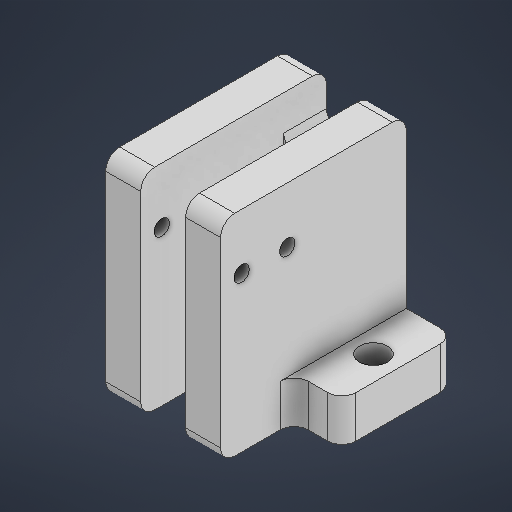
# Autodesk Inventor part: 6_06_support_detection2
Saved by Autodesk Inventor 2026 (Build 300175000, 175)
## iProperties
Created: 2025-06-18
Part Number: 6_06_support_detection2
Material: Générique
Document SubType Name: Modeling
Designer: Diogo
Density: 1 g/cm^3
Appearance: Par défaut
Author: Diogo
Autodesk Inventor part; units mm, degrees
ref_plane "YZ Plane" through (0, 0, 0) normal (1, 0, 0) x (0, 1, 0)
ref_plane "XZ Plane" through (0, 0, 0) normal (0, 1, 0) x (-1, 0, 0)
ref_plane "XY Plane" through (0, 0, 0) normal (0, 0, 1) x (1, 0, 0)
sketch "Esquisse1" plane through (0, 0, 0) normal (0, 0, 1) x (1, 0, 0)
  line L0 (0, 0) -> (11.8, 0)
  line L1 (11.8, 0) -> (11.8, 15)
  line L2 (11.8, 15) -> (18.2, 15)
  line L3 (18.2, 15) -> (18.2, 0)
  line L4 (18.2, 0) -> (30, 0)
  line L5 (30, 0) -> (30, 6)
  line L6 (30, 6) -> (23.2, 6)
  line L7 (23.2, 6) -> (23.2, 30)
  line L8 (23.2, 30) -> (18.2, 30)
  line L9 (18.2, 30) -> (18.2, 23)
  line L10 (18.2, 23) -> (11.8, 23)
  line L11 (11.8, 23) -> (11.8, 30)
  line L12 (6.8, 30) -> (6.8, 6)
  line L13 (6.8, 6) -> (0, 6)
  line L14 (0, 6) -> (0, 0)
  line L15 (0, 0) -> (11.8, 0)
  line L16 (11.8, 30) -> (6.8, 30)
  dimension "d0" = 11.8
  dimension "d1" = 15
  dimension "d2" = 6.4
  dimension "d3" = 11.8
  dimension "d4" = 6
  dimension "d5" = 6.8
  dimension "d6" = 24
  dimension "d7" = 7
  dimension "d8" = 6.8
  dimension "d9" = 5
  constraints: 34 end point, 11 point on line, 9 perpendicular, 2 horizontal, 1 collinear, 1 parallel
  measures "d0" distance of L0.start L0.end
  measures "d1" distance of L0.end L1.end
  measures "d2" distance of L1.end L2.end
  measures "d3" distance of L3.end L4.end
  measures "d4" distance of L4.end L5.end
  measures "d5" distance of L5.end L6.end
  measures "d6" distance of L6.end L7.end
  measures "d7" distance of L8.end L9.end
  measures "d8" distance of L12.end L13.end
  measures "d9" distance of L11.end L12.start
extrude "Extrusion1" add sketch "Esquisse1" along normal mid plane 26.5
sketch "Esquisse2" plane through (0, 0, 0) normal (0, 1, 0) x (-1, 0, 0)
  line L0 (0, 13.25) -> (-11.8, 13.25) projected
  line L1 (-18.2, -13.25) -> (-18.2, 13.25) projected
  line L2 (-11.8, 13.25) -> (-18.2, 13.25)
  line L3 (-18.2, 13.25) -> (-18.2, -7.15)
  line L4 (-18.2, -7.15) -> (-11.8, -7.15)
  line L5 (-11.8, -7.15) -> (-11.8, 13.25)
  line L6 (0, -13.25) -> (0, 13.25) projected
  line L7 (-6.8, -13.25) -> (-6.8, 13.25) projected
  line L8 (0, 13.25) -> (-6.8, 13.25)
  line L9 (-6.8, 13.25) -> (-6.8, 2.75)
  line L10 (-6.8, 2.75) -> (0, 2.75)
  line L11 (0, 2.75) -> (0, 13.25)
  line L12 (-30, -13.25) -> (-30, 13.25) projected
  line L13 (-23.2, -13.25) -> (-23.2, 13.25) projected
  line L14 (-30, 13.25) -> (-23.2, 13.25)
  line L15 (-23.2, 13.25) -> (-23.2, 2.75)
  line L16 (-23.2, 2.75) -> (-30, 2.75)
  line L17 (-30, 2.75) -> (-30, 13.25)
  point P0 (0, 0)
  point P1 (-18.2, 13.25)
  dimension "d12" = 20.4
  dimension "d38" = 10.5
  dimension "d39" = 10.5
  constraints: 24 end point, 6 parallel, 3 horizontal, 3 perpendicular, 3 point on line
  measures "d12" distance of L3.end L2.end
  measures "d38" distance of L9.end L8.end
  measures "d39" distance of L14.end L15.end
extrude "Extrusion2" cut sketch "Esquisse2" along normal through all
sketch "Esquisse3" plane through (0, 6, 13.25) normal (0, 1, 0) x (1, 0, 0)
  line L0 (0, 26.5) -> (0, 0) projected
  line L1 (0, 26.5) -> (6.8, 26.5) projected
  point P0 (0, 13.25)
  point P1 (3.5, 18.5)
  dimension "d23" = 3.5
  dimension "d37" = 8
  measures "d23" distance from line of L0 point (3.5, 18.5)
  measures "d37" distance from line of L1 point (3.5, 18.5)
hole "Perçage1" at (3.5, 6, -5.25) direction (0, -1, 0) diameter 4 end through all
pattern_linear "Réseau rectangulaire1" count 2 spacing 23 along (1, 0, 0) of "Perçage1"
sketch "Esquisse4" plane through (6.8, 6, 13.25) normal (-1, 0, 0) x (0, 0, 1)
  circle A0 centre (-3, 16.05) radius 1.1
  line L0 (0, 24) -> (0, 0) projected
  circle A1 centre (-9.5, 16.05) radius 1.1
  line L1 (0, -6) -> (6.0526, -6) construction
  line L2 (6.0526, -6) -> (6.0526, 20) construction
  line L3 (6.0526, 20) -> (0, 20) construction
  line L4 (0, 20) -> (0, -6) construction
  line L5 (-26.5, 24) -> (0, 24) projected
  line L6 (-21.4941, 16.05) -> (1.7379, 16.05) construction
  line L7 (-26.5, 0) -> (-26.5, 24) construction
  point P0 (-13.25, -6)
  dimension "d27" = 2.2
  dimension "d29" = 2.2
  dimension "d30" = 6.5
  dimension "d31" = 26
  dimension "d32" = 7.95
  dimension "d34" = 17
  constraints: 10 end point, 2 centre point, 2 horizontal, 2 parallel, 2 point on line, 1 perpendicular
  measures "d27" diameter of A0
  measures "d29" diameter of A1
  measures "d30" distance of A0.centre A1.centre
  measures "d31" distance of L2.end L1.end
  measures "d32" distance from line of L5 A0.centre
  measures "d34" distance from line of L7 A1.centre
extrude "Extrusion3" cut sketch "Esquisse4" against normal through all
fillet "Congé1" radius 2 6 edges at (6.8, 3, 2.75) (23.2, 3, 2.75) (18.2, 23, -10.2) (11.8, 23, -10.2) (18.2, 15, -10.2) (11.8, 15, -10.2)
fillet "Congé2" radius 2 10 edges at (0, 3, -13.25) (0, 3, 2.75) (30, 3, 2.75) (30, 3, -13.25) (9.3, 30, -13.25) (9.3, 30, 13.25) (20.7, 30, 13.25) (20.7, 30, -13.25) (9.3, 0, 13.25) (20.7, 0, 13.25)
